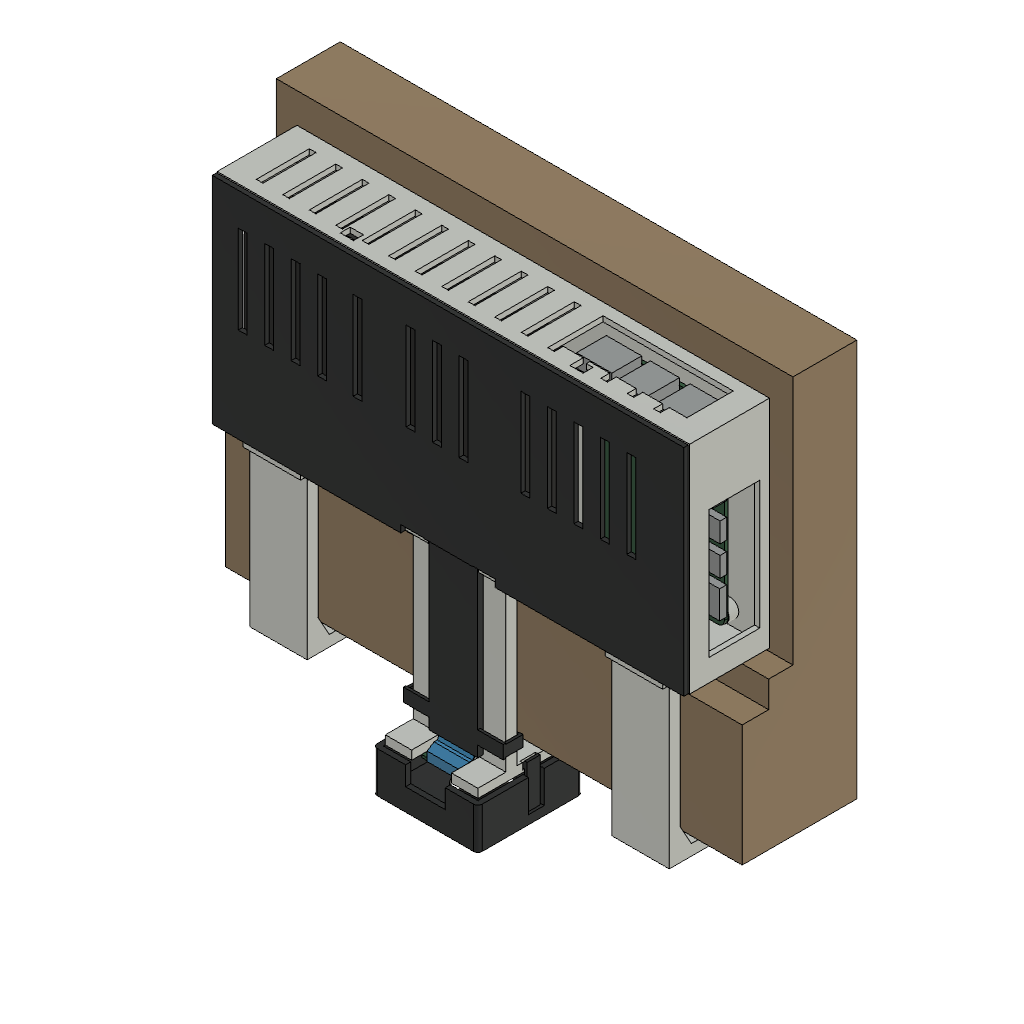
doorframe-camera-simple-v7 (Autodesk Fusion 360 design; units mm, degrees)
part number: 2026-11-08-18-06-19-159
part number: 2026-11-08-18-06-29-546
part number: 2026-11-08-18-06-30-123
part number: 2026-11-08-18-06-42-850
part number: 2026-11-08-20-43-14-141
part number: 2026-11-08-20-43-15-002
part number: 2026-11-08-20-43-15-243
part number: 2026-11-08-21-23-27-700
part number: 2026-11-08-21-23-30-854
part number: 2026-11-08-21-23-35-208
part number: 2026-11-08-21-23-36-761
part number: 2026-11-08-21-25-22-931
Autodesk Fusion 360 part; units mm, degrees
(part 1 of 2)
ref_plane "WorkPlane1" through (0, 0, 4.4) normal (0, 0, 1) x (1, 0, 0) in component "REFERENCE - INIU P51L-E2 115 x 73 x 29 mm"
sketch "INIU envelope - check supplied cable position outline" plane through (0, 0, 4.4) normal (0, 0, 1) x (1, 0, 0) in component "REFERENCE - INIU P51L-E2 115 x 73 x 29 mm"
  line L0 (11, 7.5) -> (116, 7.5)
  line L1 (121, 12.5) -> (121, 75.5)
  line L2 (116, 80.5) -> (11, 80.5)
  line L3 (6, 75.5) -> (6, 12.5)
  arc A0 (116, 7.5) -> (121, 12.5) centre (116, 12.5) ccw
  arc A1 (121, 75.5) -> (116, 80.5) centre (116, 75.5) ccw
  arc A2 (11, 80.5) -> (6, 75.5) centre (11, 75.5) ccw
  arc A3 (6, 12.5) -> (11, 7.5) centre (11, 12.5) ccw
extrude "INIU envelope - check supplied cable position" add sketch "INIU envelope - check supplied cable position outline" along normal blind 29 makes body 1 in component "REFERENCE - INIU P51L-E2 115 x 73 x 29 mm"
ref_plane "WorkPlane1" through (0, 0, 44.4) normal (0, 0, 1) x (1, 0, 0) in component "REFERENCE - Raspberry Pi4 rotated ports"
sketch "Pi PCB 85 x 56 x 1.6 outline" plane through (0, 0, 44.4) normal (0, 0, 1) x (1, 0, 0) in component "REFERENCE - Raspberry Pi4 rotated ports"
  line L0 (9, 15) -> (88, 15)
  line L1 (91, 18) -> (91, 68)
  line L2 (88, 71) -> (9, 71)
  line L3 (6, 68) -> (6, 18)
  arc A0 (88, 15) -> (91, 18) centre (88, 18) ccw
  arc A1 (91, 68) -> (88, 71) centre (88, 68) ccw
  arc A2 (9, 71) -> (6, 68) centre (9, 68) ccw
  arc A3 (6, 18) -> (9, 15) centre (9, 18) ccw
extrude "Pi PCB 85 x 56 x 1.6" add sketch "Pi PCB 85 x 56 x 1.6 outline" along normal blind 1.6 separate body makes body 2 in component "REFERENCE - Raspberry Pi4 rotated ports"
ref_plane "WorkPlane2" through (0, 0, 44.3) normal (0, 0, 1) x (1, 0, 0) in component "REFERENCE - Raspberry Pi4 rotated ports"
sketch "Pi mounting holes layout" plane through (0, 0, 44.3) normal (0, 0, 1) x (1, 0, 0) in component "REFERENCE - Raspberry Pi4 rotated ports"
  circle A0 centre (87.5, 67.5) radius 1.375
  circle A1 centre (29.5, 67.5) radius 1.375
  circle A2 centre (87.5, 18.5) radius 1.375
  circle A3 centre (29.5, 18.5) radius 1.375
extrude "Pi mounting holes" cut sketch "Pi mounting holes layout" along normal blind 2 bodies 2 in component "REFERENCE - Raspberry Pi4 rotated ports"
ref_plane "WorkPlane3" through (0, 0, 46) normal (0, 0, 1) x (1, 0, 0) in component "REFERENCE - Raspberry Pi4 rotated ports"
sketch "USB3 outline" plane through (0, 0, 46) normal (0, 0, 1) x (1, 0, 0) in component "REFERENCE - Raspberry Pi4 rotated ports"
  line L0 (3, 55.4) -> (20.5, 55.4)
  line L1 (20.5, 55.4) -> (20.5, 68.6)
  line L2 (20.5, 68.6) -> (3, 68.6)
  line L3 (3, 68.6) -> (3, 55.4)
extrude "USB3" add sketch "USB3 outline" along normal blind 16 separate body makes body 3 in component "REFERENCE - Raspberry Pi4 rotated ports"
ref_plane "WorkPlane4" through (0, 0, 46) normal (0, 0, 1) x (1, 0, 0) in component "REFERENCE - Raspberry Pi4 rotated ports"
sketch "USB2 outline" plane through (0, 0, 46) normal (0, 0, 1) x (1, 0, 0) in component "REFERENCE - Raspberry Pi4 rotated ports"
  line L0 (3, 37.4) -> (20.5, 37.4)
  line L1 (20.5, 37.4) -> (20.5, 50.6)
  line L2 (20.5, 50.6) -> (3, 50.6)
  line L3 (3, 50.6) -> (3, 37.4)
extrude "USB2" add sketch "USB2 outline" along normal blind 16 separate body makes body 4 in component "REFERENCE - Raspberry Pi4 rotated ports"
ref_plane "WorkPlane5" through (0, 0, 46) normal (0, 0, 1) x (1, 0, 0) in component "REFERENCE - Raspberry Pi4 rotated ports"
sketch "Ethernet outline" plane through (0, 0, 46) normal (0, 0, 1) x (1, 0, 0) in component "REFERENCE - Raspberry Pi4 rotated ports"
  line L0 (3, 17.5) -> (24.5, 17.5)
  line L1 (24.5, 17.5) -> (24.5, 33.5)
  line L2 (24.5, 33.5) -> (3, 33.5)
  line L3 (3, 33.5) -> (3, 17.5)
extrude "Ethernet" add sketch "Ethernet outline" along normal blind 13.5 separate body makes body 5 in component "REFERENCE - Raspberry Pi4 rotated ports"
ref_plane "WorkPlane6" through (0, 0, 46) normal (0, 0, 1) x (1, 0, 0) in component "REFERENCE - Raspberry Pi4 rotated ports"
sketch "USB-C outline" plane through (0, 0, 46) normal (0, 0, 1) x (1, 0, 0) in component "REFERENCE - Raspberry Pi4 rotated ports"
  line L0 (73.5, 64) -> (86.1, 64)
  line L1 (86.1, 64) -> (86.1, 72)
  line L2 (86.1, 72) -> (73.5, 72)
  line L3 (73.5, 72) -> (73.5, 64)
extrude "USB-C" add sketch "USB-C outline" along normal blind 3.2 separate body makes body 6 in component "REFERENCE - Raspberry Pi4 rotated ports"
ref_plane "WorkPlane7" through (0, 0, 46) normal (0, 0, 1) x (1, 0, 0) in component "REFERENCE - Raspberry Pi4 rotated ports"
sketch "HDMI0 outline" plane through (0, 0, 46) normal (0, 0, 1) x (1, 0, 0) in component "REFERENCE - Raspberry Pi4 rotated ports"
  line L0 (60.5, 64) -> (69.5, 64)
  line L1 (69.5, 64) -> (69.5, 72)
  line L2 (69.5, 72) -> (60.5, 72)
  line L3 (60.5, 72) -> (60.5, 64)
extrude "HDMI0" add sketch "HDMI0 outline" along normal blind 3 separate body makes body 7 in component "REFERENCE - Raspberry Pi4 rotated ports"
ref_plane "WorkPlane8" through (0, 0, 46) normal (0, 0, 1) x (1, 0, 0) in component "REFERENCE - Raspberry Pi4 rotated ports"
sketch "HDMI1 outline" plane through (0, 0, 46) normal (0, 0, 1) x (1, 0, 0) in component "REFERENCE - Raspberry Pi4 rotated ports"
  line L0 (47, 64) -> (56, 64)
  line L1 (56, 64) -> (56, 72)
  line L2 (56, 72) -> (47, 72)
  line L3 (47, 72) -> (47, 64)
extrude "HDMI1" add sketch "HDMI1 outline" along normal blind 3 separate body makes body 8 in component "REFERENCE - Raspberry Pi4 rotated ports"
ref_plane "WorkPlane9" through (0, 0, 46) normal (0, 0, 1) x (1, 0, 0) in component "REFERENCE - Raspberry Pi4 rotated ports"
sketch "Audio outline" plane through (0, 0, 46) normal (0, 0, 1) x (1, 0, 0) in component "REFERENCE - Raspberry Pi4 rotated ports"
  line L0 (33.5, 58) -> (40.5, 58)
  line L1 (40.5, 58) -> (40.5, 72)
  line L2 (40.5, 72) -> (33.5, 72)
  line L3 (33.5, 72) -> (33.5, 58)
extrude "Audio" add sketch "Audio outline" along normal blind 6 separate body makes body 9 in component "REFERENCE - Raspberry Pi4 rotated ports"
ref_plane "WorkPlane1" through (0, 0, 5.5) normal (0, 0, 1) x (1, 0, 0) in component "REFERENCE - Waveshare RPi Camera G PCB and lens"
sketch "Camera PCB 25 x 24 outline" plane through (0, 0, 5.5) normal (0, 0, 1) x (1, 0, 0) in component "REFERENCE - Waveshare RPi Camera G PCB and lens"
  line L0 (6.5, 6) -> (31.5, 6)
  line L1 (31.5, 6) -> (31.5, 30)
  line L2 (31.5, 30) -> (6.5, 30)
  line L3 (6.5, 30) -> (6.5, 6)
extrude "Camera PCB 25 x 24" add sketch "Camera PCB 25 x 24 outline" along normal blind 1.2 separate body makes body 10 in component "REFERENCE - Waveshare RPi Camera G PCB and lens"
ref_plane "WorkPlane2" through (0, 0, 5.4) normal (0, 0, 1) x (1, 0, 0) in component "REFERENCE - Waveshare RPi Camera G PCB and lens"
sketch "Camera mounting holes layout" plane through (0, 0, 5.4) normal (0, 0, 1) x (1, 0, 0) in component "REFERENCE - Waveshare RPi Camera G PCB and lens"
  circle A0 centre (8.5, 14.5) radius 1.1
  circle A1 centre (29.5, 14.5) radius 1.1
  circle A2 centre (8.5, 28) radius 1.1
  circle A3 centre (29.5, 28) radius 1.1
extrude "Camera mounting holes" cut sketch "Camera mounting holes layout" along normal blind 1.5 bodies 10 in component "REFERENCE - Waveshare RPi Camera G PCB and lens"
ref_plane "WorkPlane3" through (0, 0, 6.7) normal (0, 0, 1) x (1, 0, 0) in component "REFERENCE - Waveshare RPi Camera G PCB and lens"
sketch "Approximate fisheye barrel - verify height layout" plane through (0, 0, 6.7) normal (0, 0, 1) x (1, 0, 0) in component "REFERENCE - Waveshare RPi Camera G PCB and lens"
  circle A0 centre (19, 21.65) radius 8
extrude "Approximate fisheye barrel - verify height" add sketch "Approximate fisheye barrel - verify height layout" along normal blind 18 separate body makes body 11 in component "REFERENCE - Waveshare RPi Camera G PCB and lens"
ref_plane "WorkPlane1" through (0, 0, 55) normal (0, 0, 1) x (1, 0, 0) in component "REFERENCE - six mount pads - compressed"
sketch "left lower-ledge pad - 20 x 10 x 3 outline" plane through (0, 0, 55) normal (0, 0, 1) x (1, 0, 0) in component "REFERENCE - six mount pads - compressed"
  line L0 (15, 0.5) -> (35, 0.5)
  line L1 (35, 0.5) -> (35, 10.5)
  line L2 (35, 10.5) -> (15, 10.5)
  line L3 (15, 10.5) -> (15, 0.5)
extrude "left lower-ledge pad - 20 x 10 x 3" add sketch "left lower-ledge pad - 20 x 10 x 3 outline" along normal blind 2.5 separate body makes body 12 in component "REFERENCE - six mount pads - compressed"
ref_plane "WorkPlane2" through (0, 0, 67) normal (0, 0, 1) x (1, 0, 0) in component "REFERENCE - six mount pads - compressed"
sketch "left upper-ledge pad - 20 x 9 x 3 outline" plane through (0, 0, 67) normal (0, 0, 1) x (1, 0, 0) in component "REFERENCE - six mount pads - compressed"
  line L0 (15, 13) -> (35, 13)
  line L1 (35, 13) -> (35, 22)
  line L2 (35, 22) -> (15, 22)
  line L3 (15, 22) -> (15, 13)
extrude "left upper-ledge pad - 20 x 9 x 3" add sketch "left upper-ledge pad - 20 x 9 x 3 outline" along normal blind 2.5 separate body makes body 13 in component "REFERENCE - six mount pads - compressed"
ref_plane "WorkPlane3" through (0, 0, -2.5) normal (0, 0, 1) x (1, 0, 0) in component "REFERENCE - six mount pads - compressed"
sketch "left underside retaining pad - 16 x 14 x 3 outline" plane through (0, 0, -2.5) normal (0, 0, 1) x (1, 0, 0) in component "REFERENCE - six mount pads - compressed"
  line L0 (17, 30) -> (33, 30)
  line L1 (33, 30) -> (33, 44)
  line L2 (33, 44) -> (17, 44)
  line L3 (17, 44) -> (17, 30)
extrude "left underside retaining pad - 16 x 14 x 3" add sketch "left underside retaining pad - 16 x 14 x 3 outline" along normal blind 2.5 separate body makes body 14 in component "REFERENCE - six mount pads - compressed"
ref_plane "WorkPlane4" through (0, 0, 55) normal (0, 0, 1) x (1, 0, 0) in component "REFERENCE - six mount pads - compressed"
sketch "right lower-ledge pad - 20 x 10 x 3 outline" plane through (0, 0, 55) normal (0, 0, 1) x (1, 0, 0) in component "REFERENCE - six mount pads - compressed"
  line L0 (179, 0.5) -> (199, 0.5)
  line L1 (199, 0.5) -> (199, 10.5)
  line L2 (199, 10.5) -> (179, 10.5)
  line L3 (179, 10.5) -> (179, 0.5)
extrude "right lower-ledge pad - 20 x 10 x 3" add sketch "right lower-ledge pad - 20 x 10 x 3 outline" along normal blind 2.5 separate body makes body 15 in component "REFERENCE - six mount pads - compressed"
ref_plane "WorkPlane5" through (0, 0, 67) normal (0, 0, 1) x (1, 0, 0) in component "REFERENCE - six mount pads - compressed"
sketch "right upper-ledge pad - 20 x 9 x 3 outline" plane through (0, 0, 67) normal (0, 0, 1) x (1, 0, 0) in component "REFERENCE - six mount pads - compressed"
  line L0 (179, 13) -> (199, 13)
  line L1 (199, 13) -> (199, 22)
  line L2 (199, 22) -> (179, 22)
  line L3 (179, 22) -> (179, 13)
extrude "right upper-ledge pad - 20 x 9 x 3" add sketch "right upper-ledge pad - 20 x 9 x 3 outline" along normal blind 2.5 separate body makes body 16 in component "REFERENCE - six mount pads - compressed"
ref_plane "WorkPlane6" through (0, 0, -2.5) normal (0, 0, 1) x (1, 0, 0) in component "REFERENCE - six mount pads - compressed"
sketch "right underside retaining pad - 16 x 14 x 3 outline" plane through (0, 0, -2.5) normal (0, 0, 1) x (1, 0, 0) in component "REFERENCE - six mount pads - compressed"
  line L0 (181, 30) -> (197, 30)
  line L1 (197, 30) -> (197, 44)
  line L2 (197, 44) -> (181, 44)
  line L3 (181, 44) -> (181, 30)
extrude "right underside retaining pad - 16 x 14 x 3" add sketch "right underside retaining pad - 16 x 14 x 3 outline" along normal blind 2.5 separate body makes body 17 in component "REFERENCE - six mount pads - compressed"
ref_plane "WorkPlane1" through (-10, 0, 0) normal (1, 0, 0) x (0, 1, 0) in component "REFERENCE - upward-stepped frame - back wall assumed"
sketch "Corrected upward frame outline" plane through (-10, 0, 0) normal (1, 0, 0) x (0, 0, -1) in component "REFERENCE - upward-stepped frame - back wall assumed"
  line L0 (0, 0) -> (0, 52)
  line L1 (0, 52) -> (-180, 52)
  line L2 (-180, 52) -> (-180, 23)
  line L3 (-180, 23) -> (-67, 23)
  line L4 (-67, 23) -> (-67, 12)
  line L5 (-67, 12) -> (-55, 12)
  line L6 (-55, 12) -> (-55, 0)
  line L7 (-55, 0) -> (0, 0)
extrude "Corrected upward frame" add sketch "Corrected upward frame outline" along normal blind 234 separate body makes body 18 in component "REFERENCE - upward-stepped frame - back wall assumed"
ref_plane "WorkPlane1" through (245, 0, 0) normal (1, 0, 0) x (0, 1, 0) in component "07 Upward-step fit gauge PRINT FIRST - PRINT"
sketch "Profile fit gauge outline" plane through (245, 0, 0) normal (1, 0, 0) x (0, 0, -1) in component "07 Upward-step fit gauge PRINT FIRST - PRINT"
  line L0 (0, -0.6) -> (-55.6, -0.6)
  line L1 (-55.6, -0.6) -> (-55.6, 11.4)
  line L2 (-55.6, 11.4) -> (-67.6, 11.4)
  line L3 (-67.6, 11.4) -> (-67.6, 23)
  line L4 (-67.6, 23) -> (-70, 23)
  line L5 (-70, 23) -> (-70, 9)
  line L6 (-70, 9) -> (-58, 9)
  line L7 (-58, 9) -> (-58, -3)
  line L8 (-58, -3) -> (0, -3)
  line L9 (0, -3) -> (0, -0.6)
extrude "Profile fit gauge" add sketch "Profile fit gauge outline" along normal blind 8 separate body makes body 19 in component "07 Upward-step fit gauge PRINT FIRST - PRINT"
ref_plane "WorkPlane1" through (0, 0, 69) normal (0, 0, 1) x (1, 0, 0) in component "01 Integral case mount and camera holder - PRINT"
sketch "Open-front case outline" plane through (0, 0, 69) normal (0, 0, 1) x (1, 0, 0) in component "01 Integral case mount and camera holder - PRINT"
  line L0 (0, -13.8) -> (214, -13.8)
  line L1 (214, -13.8) -> (214, 22.4)
  line L2 (214, 22.4) -> (0, 22.4)
  line L3 (0, 22.4) -> (0, -13.8)
extrude "Open-front case" add sketch "Open-front case outline" along normal blind 98 separate body makes body 20 in component "01 Integral case mount and camera holder - PRINT"
ref_plane "WorkPlane2" through (0, 0, 71.4) normal (0, 0, 1) x (1, 0, 0) in component "01 Integral case mount and camera holder - PRINT"
sketch "Electronics cavity outline" plane through (0, 0, 71.4) normal (0, 0, 1) x (1, 0, 0) in component "01 Integral case mount and camera holder - PRINT"
  line L0 (2.4, -14) -> (211.6, -14)
  line L1 (211.6, -14) -> (211.6, 20)
  line L2 (211.6, 20) -> (2.4, 20)
  line L3 (2.4, 20) -> (2.4, -14)
extrude "Electronics cavity" cut sketch "Electronics cavity outline" along normal blind 93.2 bodies 20 in component "01 Integral case mount and camera holder - PRINT"
ref_plane "WorkPlane3" through (0, 20, 0) normal (0, 1, 0) x (0, 0, 1) in component "01 Integral case mount and camera holder - PRINT"
sketch "Pi heat-set bosses - 8 mm OD layout" plane through (0, 20, 0) normal (0, 1, 0) x (1, 0, 0) in component "01 Integral case mount and camera holder - PRINT"
  circle A0 centre (149.5, -78.5) radius 4
  circle A1 centre (198.5, -78.5) radius 4
  circle A2 centre (149.5, -136.5) radius 4
  circle A3 centre (198.5, -136.5) radius 4
extrude "Pi heat-set bosses - 8 mm OD" add sketch "Pi heat-set bosses - 8 mm OD layout" against normal blind 4.4 bodies 20 in component "01 Integral case mount and camera holder - PRINT"
ref_plane "WorkPlane4" through (0, 15.6, 0) normal (0, 1, 0) x (0, 0, 1) in component "01 Integral case mount and camera holder - PRINT"
sketch "Pi M2.5 insert pockets - 4 mm x 5 mm layout" plane through (0, 15.6, 0) normal (0, 1, 0) x (1, 0, 0) in component "01 Integral case mount and camera holder - PRINT"
  circle A0 centre (149.5, -78.5) radius 2
  circle A1 centre (198.5, -78.5) radius 2
  circle A2 centre (149.5, -136.5) radius 2
  circle A3 centre (198.5, -136.5) radius 2
extrude "Pi M2.5 insert pockets - 4 mm x 5 mm" cut sketch "Pi M2.5 insert pockets - 4 mm x 5 mm layout" along normal blind 5 bodies 20 in component "01 Integral case mount and camera holder - PRINT"
ref_plane "WorkPlane5" through (0, 0, 79) normal (0, 0, 1) x (1, 0, 0) in component "01 Integral case mount and camera holder - PRINT"
sketch "Pi power HDMI and audio side access outline" plane through (0, 0, 79) normal (0, 0, 1) x (1, 0, 0) in component "01 Integral case mount and camera holder - PRINT"
  line L0 (210.8, -5) -> (215, -5)
  line L1 (215, -5) -> (215, 18)
  line L2 (215, 18) -> (210.8, 18)
  line L3 (210.8, 18) -> (210.8, -5)
extrude "Pi power HDMI and audio side access" cut sketch "Pi power HDMI and audio side access outline" along normal blind 58 bodies 20 in component "01 Integral case mount and camera holder - PRINT"
ref_plane "WorkPlane6" through (0, 0, 75) normal (0, 0, 1) x (1, 0, 0) in component "01 Integral case mount and camera holder - PRINT"
sketch "Battery charging-end access outline" plane through (0, 0, 75) normal (0, 0, 1) x (1, 0, 0) in component "01 Integral case mount and camera holder - PRINT"
  line L0 (-1, -11.5) -> (3.2, -11.5)
  line L1 (3.2, -11.5) -> (3.2, 20.5)
  line L2 (3.2, 20.5) -> (-1, 20.5)
  line L3 (-1, 20.5) -> (-1, -11.5)
extrude "Battery charging-end access" cut sketch "Battery charging-end access outline" along normal blind 77 bodies 20 in component "01 Integral case mount and camera holder - PRINT"
ref_plane "WorkPlane7" through (0, 0, 164.5) normal (0, 0, 1) x (1, 0, 0) in component "01 Integral case mount and camera holder - PRINT"
sketch "Roof vents layout" plane through (0, 0, 164.5) normal (0, 0, 1) x (1, 0, 0) in component "01 Integral case mount and camera holder - PRINT"
  line L0 (12, -8) -> (15, -8)
  line L1 (15, -8) -> (15, 16)
  line L2 (15, 16) -> (12, 16)
  line L3 (12, 16) -> (12, -8)
  line L4 (24, -8) -> (27, -8)
  line L5 (27, -8) -> (27, 16)
  line L6 (27, 16) -> (24, 16)
  line L7 (24, 16) -> (24, -8)
  line L8 (36, -8) -> (39, -8)
  line L9 (39, -8) -> (39, 16)
  line L10 (39, 16) -> (36, 16)
  line L11 (36, 16) -> (36, -8)
  line L12 (48, -8) -> (51, -8)
  line L13 (51, -8) -> (51, 16)
  line L14 (51, 16) -> (48, 16)
  line L15 (48, 16) -> (48, -8)
  line L16 (60, -8) -> (63, -8)
  line L17 (63, -8) -> (63, 16)
  line L18 (63, 16) -> (60, 16)
  line L19 (60, 16) -> (60, -8)
  line L20 (72, -8) -> (75, -8)
  line L21 (75, -8) -> (75, 16)
  line L22 (75, 16) -> (72, 16)
  line L23 (72, 16) -> (72, -8)
  line L24 (84, -8) -> (87, -8)
  line L25 (87, -8) -> (87, 16)
  line L26 (87, 16) -> (84, 16)
  line L27 (84, 16) -> (84, -8)
  line L28 (96, -8) -> (99, -8)
  line L29 (99, -8) -> (99, 16)
  line L30 (99, 16) -> (96, 16)
  line L31 (96, 16) -> (96, -8)
  line L32 (108, -8) -> (111, -8)
  line L33 (111, -8) -> (111, 16)
  line L34 (111, 16) -> (108, 16)
  line L35 (108, 16) -> (108, -8)
  line L36 (120, -8) -> (123, -8)
  line L37 (123, -8) -> (123, 16)
  line L38 (123, 16) -> (120, 16)
  line L39 (120, 16) -> (120, -8)
  line L40 (132, -8) -> (135, -8)
  line L41 (135, -8) -> (135, 16)
  line L42 (135, 16) -> (132, 16)
  line L43 (132, 16) -> (132, -8)
  line L44 (144, -8) -> (147, -8)
  line L45 (147, -8) -> (147, 16)
  line L46 (147, 16) -> (144, 16)
  line L47 (144, 16) -> (144, -8)
  line L48 (156, -8) -> (159, -8)
  line L49 (159, -8) -> (159, 16)
  line L50 (159, 16) -> (156, 16)
  line L51 (156, 16) -> (156, -8)
  line L52 (168, -8) -> (171, -8)
  line L53 (171, -8) -> (171, 16)
  line L54 (171, 16) -> (168, 16)
  line L55 (168, 16) -> (168, -8)
  line L56 (180, -8) -> (183, -8)
  line L57 (183, -8) -> (183, 16)
  line L58 (183, 16) -> (180, 16)
  line L59 (180, 16) -> (180, -8)
  line L60 (192, -8) -> (195, -8)
  line L61 (195, -8) -> (195, 16)
  line L62 (195, 16) -> (192, 16)
  line L63 (192, 16) -> (192, -8)
extrude "Roof vents" cut sketch "Roof vents layout" along normal blind 2.6 bodies 20 in component "01 Integral case mount and camera holder - PRINT"
ref_plane "WorkPlane8" through (0, 0, 164.5) normal (0, 0, 1) x (1, 0, 0) in component "01 Integral case mount and camera holder - PRINT"
sketch "Pi USB and Ethernet top access outline" plane through (0, 0, 164.5) normal (0, 0, 1) x (1, 0, 0) in component "01 Integral case mount and camera holder - PRINT"
  line L0 (144, -4) -> (203, -4)
  line L1 (203, -4) -> (203, 17)
  line L2 (203, 17) -> (144, 17)
  line L3 (144, 17) -> (144, -4)
extrude "Pi USB and Ethernet top access" cut sketch "Pi USB and Ethernet top access outline" along normal blind 2.6 bodies 20 in component "01 Integral case mount and camera holder - PRINT"
ref_plane "WorkPlane9" through (0, 0, 68.9) normal (0, 0, 1) x (1, 0, 0) in component "01 Integral case mount and camera holder - PRINT"
sketch "Battery strap slots layout" plane through (0, 0, 68.9) normal (0, 0, 1) x (1, 0, 0) in component "01 Integral case mount and camera holder - PRINT"
  line L0 (38, -10.8) -> (50, -10.8)
  line L1 (50, -10.8) -> (50, -8.6)
  line L2 (50, -8.6) -> (38, -8.6)
  line L3 (38, -8.6) -> (38, -10.8)
  line L4 (38, 18.6) -> (50, 18.6)
  line L5 (50, 18.6) -> (50, 20.8)
  line L6 (50, 20.8) -> (38, 20.8)
  line L7 (38, 20.8) -> (38, 18.6)
  line L8 (80, -10.8) -> (92, -10.8)
  line L9 (92, -10.8) -> (92, -8.6)
  line L10 (92, -8.6) -> (80, -8.6)
  line L11 (80, -8.6) -> (80, -10.8)
  line L12 (80, 18.6) -> (92, 18.6)
  line L13 (92, 18.6) -> (92, 20.8)
  line L14 (92, 20.8) -> (80, 20.8)
  line L15 (80, 20.8) -> (80, 18.6)
extrude "Battery strap slots" cut sketch "Battery strap slots layout" along normal blind 2.6 bodies 20 in component "01 Integral case mount and camera holder - PRINT"
ref_plane "WorkPlane10" through (0, 0, 57.5) normal (0, 0, 1) x (1, 0, 0) in component "01 Integral case mount and camera holder - PRINT"
sketch "First-ledge foot 1 outline" plane through (0, 0, 57.5) normal (0, 0, 1) x (1, 0, 0) in component "01 Integral case mount and camera holder - PRINT"
  line L0 (15, 0.5) -> (35, 0.5)
  line L1 (35, 0.5) -> (35, 10.5)
  line L2 (35, 10.5) -> (15, 10.5)
  line L3 (15, 10.5) -> (15, 0.5)
extrude "First-ledge foot 1" add sketch "First-ledge foot 1 outline" along normal blind 11.5 bodies 20 in component "01 Integral case mount and camera holder - PRINT"
ref_plane "WorkPlane11" through (0, 0, 65) normal (0, 0, 1) x (1, 0, 0) in component "01 Integral case mount and camera holder - PRINT"
sketch "Integral arm root 1 outline" plane through (0, 0, 65) normal (0, 0, 1) x (1, 0, 0) in component "01 Integral case mount and camera holder - PRINT"
  line L0 (12, -14) -> (38, -14)
  line L1 (38, -14) -> (38, -3)
  line L2 (38, -3) -> (12, -3)
  line L3 (12, -3) -> (12, -14)
extrude "Integral arm root 1" add sketch "Integral arm root 1 outline" along normal blind 4.2 bodies 20 in component "01 Integral case mount and camera holder - PRINT"
ref_plane "WorkPlane12" through (12, 0, 0) normal (1, 0, 0) x (0, 1, 0) in component "01 Integral case mount and camera holder - PRINT"
sketch "Integral retaining arm 1 outline" plane through (12, 0, 0) normal (1, 0, 0) x (0, 0, -1) in component "01 Integral case mount and camera holder - PRINT"
  line L0 (7, -11) -> (7, 45)
  line L1 (7, 45) -> (2, 45)
  line L2 (2, 45) -> (2, -1)
  line L3 (2, -1) -> (-7, -6)
  line L4 (-7, -6) -> (-66, -6)
  line L5 (-66, -6) -> (-66, -11)
  line L6 (-66, -11) -> (7, -11)
extrude "Integral retaining arm 1" add sketch "Integral retaining arm 1 outline" along normal blind 26 bodies 20 in component "01 Integral case mount and camera holder - PRINT"
ref_plane "WorkPlane13" through (0, 0, -2.5) normal (0, 0, 1) x (1, 0, 0) in component "01 Integral case mount and camera holder - PRINT"
sketch "Underside pad pocket 1 layout" plane through (0, 0, -2.5) normal (0, 0, 1) x (1, 0, 0) in component "01 Integral case mount and camera holder - PRINT"
  line L0 (17, 30) -> (33, 30)
  line L1 (33, 30) -> (33, 44)
  line L2 (33, 44) -> (17, 44)
  line L3 (17, 44) -> (17, 30)
extrude "Underside pad pocket 1" cut sketch "Underside pad pocket 1 layout" along normal blind 0.6 bodies 20 in component "01 Integral case mount and camera holder - PRINT"
ref_plane "WorkPlane14" through (11.9, 0, 0) normal (1, 0, 0) x (0, 1, 0) in component "01 Integral case mount and camera holder - PRINT"
sketch "Arm lead-in 1 outline" plane through (11.9, 0, 0) normal (1, 0, 0) x (0, 0, -1) in component "01 Integral case mount and camera holder - PRINT"
  line L0 (2, 44.5) -> (2, 45)
  line L1 (2, 45) -> (2.5, 45)
  line L2 (2.5, 45) -> (2, 44.5)
extrude "Arm lead-in 1" cut sketch "Arm lead-in 1 outline" along normal blind 26.2 bodies 20 in component "01 Integral case mount and camera holder - PRINT"
ref_plane "WorkPlane15" through (0, 0, 57.5) normal (0, 0, 1) x (1, 0, 0) in component "01 Integral case mount and camera holder - PRINT"
sketch "First-ledge foot 2 outline" plane through (0, 0, 57.5) normal (0, 0, 1) x (1, 0, 0) in component "01 Integral case mount and camera holder - PRINT"
  line L0 (179, 0.5) -> (199, 0.5)
  line L1 (199, 0.5) -> (199, 10.5)
  line L2 (199, 10.5) -> (179, 10.5)
  line L3 (179, 10.5) -> (179, 0.5)
extrude "First-ledge foot 2" add sketch "First-ledge foot 2 outline" along normal blind 11.5 bodies 20 in component "01 Integral case mount and camera holder - PRINT"
ref_plane "WorkPlane16" through (0, 0, 65) normal (0, 0, 1) x (1, 0, 0) in component "01 Integral case mount and camera holder - PRINT"
sketch "Integral arm root 2 outline" plane through (0, 0, 65) normal (0, 0, 1) x (1, 0, 0) in component "01 Integral case mount and camera holder - PRINT"
  line L0 (176, -14) -> (202, -14)
  line L1 (202, -14) -> (202, -3)
  line L2 (202, -3) -> (176, -3)
  line L3 (176, -3) -> (176, -14)
extrude "Integral arm root 2" add sketch "Integral arm root 2 outline" along normal blind 4.2 bodies 20 in component "01 Integral case mount and camera holder - PRINT"
ref_plane "WorkPlane17" through (176, 0, 0) normal (1, 0, 0) x (0, 1, 0) in component "01 Integral case mount and camera holder - PRINT"
sketch "Integral retaining arm 2 outline" plane through (176, 0, 0) normal (1, 0, 0) x (0, 0, -1) in component "01 Integral case mount and camera holder - PRINT"
  line L0 (7, -11) -> (7, 45)
  line L1 (7, 45) -> (2, 45)
  line L2 (2, 45) -> (2, -1)
  line L3 (2, -1) -> (-7, -6)
  line L4 (-7, -6) -> (-66, -6)
  line L5 (-66, -6) -> (-66, -11)
  line L6 (-66, -11) -> (7, -11)
extrude "Integral retaining arm 2" add sketch "Integral retaining arm 2 outline" along normal blind 26 bodies 20 in component "01 Integral case mount and camera holder - PRINT"
ref_plane "WorkPlane18" through (0, 0, -2.5) normal (0, 0, 1) x (1, 0, 0) in component "01 Integral case mount and camera holder - PRINT"
sketch "Underside pad pocket 2 layout" plane through (0, 0, -2.5) normal (0, 0, 1) x (1, 0, 0) in component "01 Integral case mount and camera holder - PRINT"
  line L0 (181, 30) -> (197, 30)
  line L1 (197, 30) -> (197, 44)
  line L2 (197, 44) -> (181, 44)
  line L3 (181, 44) -> (181, 30)
extrude "Underside pad pocket 2" cut sketch "Underside pad pocket 2 layout" along normal blind 0.6 bodies 20 in component "01 Integral case mount and camera holder - PRINT"
ref_plane "WorkPlane19" through (175.9, 0, 0) normal (1, 0, 0) x (0, 1, 0) in component "01 Integral case mount and camera holder - PRINT"
sketch "Arm lead-in 2 outline" plane through (175.9, 0, 0) normal (1, 0, 0) x (0, 0, -1) in component "01 Integral case mount and camera holder - PRINT"
  line L0 (2, 44.5) -> (2, 45)
  line L1 (2, 45) -> (2.5, 45)
  line L2 (2.5, 45) -> (2, 44.5)
extrude "Arm lead-in 2" cut sketch "Arm lead-in 2 outline" along normal blind 26.2 bodies 20 in component "01 Integral case mount and camera holder - PRINT"
ref_plane "WorkPlane20" through (0, 0, 68.9) normal (0, 0, 1) x (1, 0, 0) in component "01 Integral case mount and camera holder - PRINT"
sketch "Upper-ledge pad recesses layout" plane through (0, 0, 68.9) normal (0, 0, 1) x (1, 0, 0) in component "01 Integral case mount and camera holder - PRINT"
  line L0 (15, 13) -> (35, 13)
  line L1 (35, 13) -> (35, 22)
  line L2 (35, 22) -> (15, 22)
  line L3 (15, 22) -> (15, 13)
  line L4 (179, 13) -> (199, 13)
  line L5 (199, 13) -> (199, 22)
  line L6 (199, 22) -> (179, 22)
  line L7 (179, 22) -> (179, 13)
extrude "Upper-ledge pad recesses" cut sketch "Upper-ledge pad recesses layout" along normal blind 0.6 bodies 20 in component "01 Integral case mount and camera holder - PRINT"
ref_plane "WorkPlane21" through (0, 0, 68.9) normal (0, 0, 1) x (1, 0, 0) in component "01 Integral case mount and camera holder - PRINT"
sketch "Bottom cover latch window 55 outline" plane through (0, 0, 68.9) normal (0, 0, 1) x (1, 0, 0) in component "01 Integral case mount and camera holder - PRINT"
  line L0 (52, -5) -> (58, -5)
  line L1 (58, -5) -> (58, -0.5)
  line L2 (58, -0.5) -> (52, -0.5)
  line L3 (52, -0.5) -> (52, -5)
extrude "Bottom cover latch window 55" cut sketch "Bottom cover latch window 55 outline" along normal blind 2.6 bodies 20 in component "01 Integral case mount and camera holder - PRINT"
ref_plane "WorkPlane22" through (0, 0, 164.5) normal (0, 0, 1) x (1, 0, 0) in component "01 Integral case mount and camera holder - PRINT"
sketch "Top cover latch window 55 outline" plane through (0, 0, 164.5) normal (0, 0, 1) x (1, 0, 0) in component "01 Integral case mount and camera holder - PRINT"
  line L0 (52, -10) -> (58, -10)
  line L1 (58, -10) -> (58, -5.5)
  line L2 (58, -5.5) -> (52, -5.5)
  line L3 (52, -5.5) -> (52, -10)
extrude "Top cover latch window 55" cut sketch "Top cover latch window 55 outline" along normal blind 2.6 bodies 20 in component "01 Integral case mount and camera holder - PRINT"
ref_plane "WorkPlane23" through (0, 0, 68.9) normal (0, 0, 1) x (1, 0, 0) in component "01 Integral case mount and camera holder - PRINT"
sketch "Bottom cover latch window 159 outline" plane through (0, 0, 68.9) normal (0, 0, 1) x (1, 0, 0) in component "01 Integral case mount and camera holder - PRINT"
  line L0 (156, -5) -> (162, -5)
  line L1 (162, -5) -> (162, -0.5)
  line L2 (162, -0.5) -> (156, -0.5)
  line L3 (156, -0.5) -> (156, -5)
extrude "Bottom cover latch window 159" cut sketch "Bottom cover latch window 159 outline" along normal blind 2.6 bodies 20 in component "01 Integral case mount and camera holder - PRINT"
ref_plane "WorkPlane24" through (0, 0, 164.5) normal (0, 0, 1) x (1, 0, 0) in component "01 Integral case mount and camera holder - PRINT"
sketch "Top cover latch window 159 outline" plane through (0, 0, 164.5) normal (0, 0, 1) x (1, 0, 0) in component "01 Integral case mount and camera holder - PRINT"
  line L0 (156, -10) -> (162, -10)
  line L1 (162, -10) -> (162, -5.5)
  line L2 (162, -5.5) -> (156, -5.5)
  line L3 (156, -5.5) -> (156, -10)
extrude "Top cover latch window 159" cut sketch "Top cover latch window 159 outline" along normal blind 2.6 bodies 20 in component "01 Integral case mount and camera holder - PRINT"
ref_plane "WorkPlane25" through (0, 0, 69) normal (0, 0, 1) x (1, 0, 0) in component "01 Integral case mount and camera holder - PRINT"
sketch "Camera stem floor connection outline" plane through (0, 0, 69) normal (0, 0, 1) x (1, 0, 0) in component "01 Integral case mount and camera holder - PRINT"
  line L0 (86, -11) -> (128, -11)
  line L1 (128, -11) -> (128, -5)
  line L2 (128, -5) -> (86, -5)
  line L3 (86, -5) -> (86, -11)
extrude "Camera stem floor connection" add sketch "Camera stem floor connection outline" along normal blind 3 bodies 20 in component "01 Integral case mount and camera holder - PRINT"
ref_plane "WorkPlane26" through (0, 0, -6) normal (0, 0, 1) x (1, 0, 0) in component "01 Integral case mount and camera holder - PRINT"
sketch "Flush camera stem outline" plane through (0, 0, -6) normal (0, 0, 1) x (1, 0, 0) in component "01 Integral case mount and camera holder - PRINT"
  line L0 (86, -11) -> (128, -11)
  line L1 (128, -11) -> (128, -6)
  line L2 (128, -6) -> (86, -6)
  line L3 (86, -6) -> (86, -11)
extrude "Flush camera stem" add sketch "Flush camera stem outline" along normal blind 75.2 bodies 20 in component "01 Integral case mount and camera holder - PRINT"
ref_plane "WorkPlane27" through (0, 0, -10) normal (0, 0, 1) x (1, 0, 0) in component "01 Integral case mount and camera holder - PRINT"
sketch "Integral camera backplate outline" plane through (0, 0, -10) normal (0, 0, 1) x (1, 0, 0) in component "01 Integral case mount and camera holder - PRINT"
  line L0 (86, -23.65) -> (128, -23.65)
  line L1 (128, -23.65) -> (128, 18.35)
  line L2 (128, 18.35) -> (86, 18.35)
  line L3 (86, 18.35) -> (86, -23.65)
extrude "Integral camera backplate" add sketch "Integral camera backplate outline" along normal blind 4 bodies 20 in component "01 Integral case mount and camera holder - PRINT"
ref_plane "WorkPlane28" through (0, 0, -13.5) normal (0, 0, 1) x (1, 0, 0) in component "01 Integral case mount and camera holder - PRINT"
sketch "Camera M2 insert bosses - 6.4 mm OD layout" plane through (0, 0, -13.5) normal (0, 0, 1) x (1, 0, 0) in component "01 Integral case mount and camera holder - PRINT"
  circle A0 centre (117.5, -7.15) radius 3.2
  circle A1 centre (117.5, 6.35) radius 3.2
  circle A2 centre (96.5, -7.15) radius 3.2
  circle A3 centre (96.5, 6.35) radius 3.2
extrude "Camera M2 insert bosses - 6.4 mm OD" add sketch "Camera M2 insert bosses - 6.4 mm OD layout" along normal blind 3.5 bodies 20 in component "01 Integral case mount and camera holder - PRINT"
ref_plane "WorkPlane29" through (0, 0, -13.5) normal (0, 0, 1) x (1, 0, 0) in component "01 Integral case mount and camera holder - PRINT"
sketch "Camera M2 insert pockets - 3.2 mm x 4 mm layout" plane through (0, 0, -13.5) normal (0, 0, 1) x (1, 0, 0) in component "01 Integral case mount and camera holder - PRINT"
  circle A0 centre (117.5, -7.15) radius 1.6
  circle A1 centre (117.5, 6.35) radius 1.6
  circle A2 centre (96.5, -7.15) radius 1.6
  circle A3 centre (96.5, 6.35) radius 1.6
extrude "Camera M2 insert pockets - 3.2 mm x 4 mm" cut sketch "Camera M2 insert pockets - 3.2 mm x 4 mm layout" along normal blind 4 bodies 20 in component "01 Integral case mount and camera holder - PRINT"
ref_plane "WorkPlane30" through (0, 0, -10.1) normal (0, 0, 1) x (1, 0, 0) in component "01 Integral case mount and camera holder - PRINT"
sketch "Ribbon lower turn opening outline" plane through (0, 0, -10.1) normal (0, 0, 1) x (1, 0, 0) in component "01 Integral case mount and camera holder - PRINT"
  line L0 (98, -24) -> (116, -24)
  line L1 (116, -24) -> (116, -11.5)
  line L2 (116, -11.5) -> (98, -11.5)
  line L3 (98, -11.5) -> (98, -24)
extrude "Ribbon lower turn opening" cut sketch "Ribbon lower turn opening outline" along normal blind 4.2 bodies 20 in component "01 Integral case mount and camera holder - PRINT"
ref_plane "WorkPlane31" through (0, 0, -6) normal (0, 0, 1) x (1, 0, 0) in component "01 Integral case mount and camera holder - PRINT"
sketch "Recessed ribbon channel outline" plane through (0, 0, -6) normal (0, 0, 1) x (1, 0, 0) in component "01 Integral case mount and camera holder - PRINT"
  line L0 (98, -11.1) -> (116, -11.1)
  line L1 (116, -11.1) -> (116, -9.4)
  line L2 (116, -9.4) -> (98, -9.4)
  line L3 (98, -9.4) -> (98, -11.1)
extrude "Recessed ribbon channel" cut sketch "Recessed ribbon channel outline" along normal blind 75 bodies 20 in component "01 Integral case mount and camera holder - PRINT"
ref_plane "WorkPlane32" through (98, 0, 0) normal (1, 0, 0) x (0, 1, 0) in component "01 Integral case mount and camera holder - PRINT"
sketch "Ribbon entry guide ramp outline" plane through (98, 0, 0) normal (1, 0, 0) x (0, 0, -1) in component "01 Integral case mount and camera holder - PRINT"
  line L0 (-63, -9.4) -> (-69, -9.4)
  line L1 (-69, -9.4) -> (-69, -10)
  line L2 (-69, -10) -> (-63, -9.4)
extrude "Ribbon entry guide ramp" add sketch "Ribbon entry guide ramp outline" along normal blind 18 bodies 20 in component "01 Integral case mount and camera holder - PRINT"
ref_plane "WorkPlane33" through (0, 0, 68.9) normal (0, 0, 1) x (1, 0, 0) in component "01 Integral case mount and camera holder - PRINT"
sketch "Covered ribbon entry through floor outline" plane through (0, 0, 68.9) normal (0, 0, 1) x (1, 0, 0) in component "01 Integral case mount and camera holder - PRINT"
  line L0 (95.6, -14) -> (118.4, -14)
  line L1 (118.4, -14) -> (118.4, -9.8)
  line L2 (118.4, -9.8) -> (95.6, -9.8)
  line L3 (95.6, -9.8) -> (95.6, -14)
extrude "Covered ribbon entry through floor" cut sketch "Covered ribbon entry through floor outline" along normal blind 3.2 bodies 20 in component "01 Integral case mount and camera holder - PRINT"
ref_plane "WorkPlane34" through (0, 0, -9) normal (0, 0, 1) x (1, 0, 0) in component "01 Integral case mount and camera holder - PRINT"
sketch "L camera guard latch pocket outline" plane through (0, 0, -9) normal (0, 0, 1) x (1, 0, 0) in component "01 Integral case mount and camera holder - PRINT"
  line L0 (85.9, -3.4) -> (87.1, -3.4)
  line L1 (87.1, -3.4) -> (87.1, 3.4)
  line L2 (87.1, 3.4) -> (85.9, 3.4)
  line L3 (85.9, 3.4) -> (85.9, -3.4)
extrude "L camera guard latch pocket" cut sketch "L camera guard latch pocket outline" along normal blind 3.1 bodies 20 in component "01 Integral case mount and camera holder - PRINT"
ref_plane "WorkPlane35" through (0, 0, -9) normal (0, 0, 1) x (1, 0, 0) in component "01 Integral case mount and camera holder - PRINT"
sketch "R camera guard latch pocket outline" plane through (0, 0, -9) normal (0, 0, 1) x (1, 0, 0) in component "01 Integral case mount and camera holder - PRINT"
  line L0 (126.9, -3.4) -> (128.1, -3.4)
  line L1 (128.1, -3.4) -> (128.1, 3.4)
  line L2 (128.1, 3.4) -> (126.9, 3.4)
  line L3 (126.9, 3.4) -> (126.9, -3.4)
extrude "R camera guard latch pocket" cut sketch "R camera guard latch pocket outline" along normal blind 3.1 bodies 20 in component "01 Integral case mount and camera holder - PRINT"
ref_plane "WorkPlane1" through (0, 0, 69.2) normal (0, 0, 1) x (1, 0, 0) in component "02 Snap-on front cover - PRINT"
sketch "Front cover outline" plane through (0, 0, 69.2) normal (0, 0, 1) x (1, 0, 0) in component "02 Snap-on front cover - PRINT"
  line L0 (0.2, -16.2) -> (213.8, -16.2)
  line L1 (213.8, -16.2) -> (213.8, -14.2)
  line L2 (213.8, -14.2) -> (0.2, -14.2)
  line L3 (0.2, -14.2) -> (0.2, -16.2)
extrude "Front cover" add sketch "Front cover outline" along normal blind 97.6 separate body makes body 21 in component "02 Snap-on front cover - PRINT"
ref_plane "WorkPlane2" through (0, 0, 69.1) normal (0, 0, 1) x (1, 0, 0) in component "02 Snap-on front cover - PRINT"
sketch "Clearance over integral camera root outline" plane through (0, 0, 69.1) normal (0, 0, 1) x (1, 0, 0) in component "02 Snap-on front cover - PRINT"
  line L0 (85.6, -16.3) -> (128.4, -16.3)
  line L1 (128.4, -16.3) -> (128.4, -14.1)
  line L2 (128.4, -14.1) -> (85.6, -14.1)
  line L3 (85.6, -14.1) -> (85.6, -16.3)
extrude "Clearance over integral camera root" cut sketch "Clearance over integral camera root outline" along normal blind 3.4 bodies 21 in component "02 Snap-on front cover - PRINT"
ref_plane "WorkPlane3" through (0, 0, 112) normal (0, 0, 1) x (1, 0, 0) in component "02 Snap-on front cover - PRINT"
sketch "Front air slot 12 outline" plane through (0, 0, 112) normal (0, 0, 1) x (1, 0, 0) in component "02 Snap-on front cover - PRINT"
  line L0 (12, -16.3) -> (16, -16.3)
  line L1 (16, -16.3) -> (16, -14.1)
  line L2 (16, -14.1) -> (12, -14.1)
  line L3 (12, -14.1) -> (12, -16.3)
extrude "Front air slot 12" cut sketch "Front air slot 12 outline" along normal blind 40 bodies 21 in component "02 Snap-on front cover - PRINT"
ref_plane "WorkPlane4" through (0, 0, 112) normal (0, 0, 1) x (1, 0, 0) in component "02 Snap-on front cover - PRINT"
sketch "Front air slot 24 outline" plane through (0, 0, 112) normal (0, 0, 1) x (1, 0, 0) in component "02 Snap-on front cover - PRINT"
  line L0 (24, -16.3) -> (28, -16.3)
  line L1 (28, -16.3) -> (28, -14.1)
  line L2 (28, -14.1) -> (24, -14.1)
  line L3 (24, -14.1) -> (24, -16.3)
extrude "Front air slot 24" cut sketch "Front air slot 24 outline" along normal blind 40 bodies 21 in component "02 Snap-on front cover - PRINT"
ref_plane "WorkPlane5" through (0, 0, 112) normal (0, 0, 1) x (1, 0, 0) in component "02 Snap-on front cover - PRINT"
sketch "Front air slot 36 outline" plane through (0, 0, 112) normal (0, 0, 1) x (1, 0, 0) in component "02 Snap-on front cover - PRINT"
  line L0 (36, -16.3) -> (40, -16.3)
  line L1 (40, -16.3) -> (40, -14.1)
  line L2 (40, -14.1) -> (36, -14.1)
  line L3 (36, -14.1) -> (36, -16.3)
extrude "Front air slot 36" cut sketch "Front air slot 36 outline" along normal blind 40 bodies 21 in component "02 Snap-on front cover - PRINT"
ref_plane "WorkPlane6" through (0, 0, 112) normal (0, 0, 1) x (1, 0, 0) in component "02 Snap-on front cover - PRINT"
sketch "Front air slot 48 outline" plane through (0, 0, 112) normal (0, 0, 1) x (1, 0, 0) in component "02 Snap-on front cover - PRINT"
  line L0 (48, -16.3) -> (52, -16.3)
  line L1 (52, -16.3) -> (52, -14.1)
  line L2 (52, -14.1) -> (48, -14.1)
  line L3 (48, -14.1) -> (48, -16.3)
extrude "Front air slot 48" cut sketch "Front air slot 48 outline" along normal blind 40 bodies 21 in component "02 Snap-on front cover - PRINT"
ref_plane "WorkPlane7" through (0, 0, 112) normal (0, 0, 1) x (1, 0, 0) in component "02 Snap-on front cover - PRINT"
sketch "Front air slot 64 outline" plane through (0, 0, 112) normal (0, 0, 1) x (1, 0, 0) in component "02 Snap-on front cover - PRINT"
  line L0 (64, -16.3) -> (68, -16.3)
  line L1 (68, -16.3) -> (68, -14.1)
  line L2 (68, -14.1) -> (64, -14.1)
  line L3 (64, -14.1) -> (64, -16.3)
extrude "Front air slot 64" cut sketch "Front air slot 64 outline" along normal blind 40 bodies 21 in component "02 Snap-on front cover - PRINT"
ref_plane "WorkPlane8" through (0, 0, 112) normal (0, 0, 1) x (1, 0, 0) in component "02 Snap-on front cover - PRINT"
sketch "Front air slot 88 outline" plane through (0, 0, 112) normal (0, 0, 1) x (1, 0, 0) in component "02 Snap-on front cover - PRINT"
  line L0 (88, -16.3) -> (92, -16.3)
  line L1 (92, -16.3) -> (92, -14.1)
  line L2 (92, -14.1) -> (88, -14.1)
  line L3 (88, -14.1) -> (88, -16.3)
extrude "Front air slot 88" cut sketch "Front air slot 88 outline" along normal blind 40 bodies 21 in component "02 Snap-on front cover - PRINT"
ref_plane "WorkPlane9" through (0, 0, 112) normal (0, 0, 1) x (1, 0, 0) in component "02 Snap-on front cover - PRINT"
sketch "Front air slot 100 outline" plane through (0, 0, 112) normal (0, 0, 1) x (1, 0, 0) in component "02 Snap-on front cover - PRINT"
  line L0 (100, -16.3) -> (104, -16.3)
  line L1 (104, -16.3) -> (104, -14.1)
  line L2 (104, -14.1) -> (100, -14.1)
  line L3 (100, -14.1) -> (100, -16.3)
extrude "Front air slot 100" cut sketch "Front air slot 100 outline" along normal blind 40 bodies 21 in component "02 Snap-on front cover - PRINT"
ref_plane "WorkPlane10" through (0, 0, 112) normal (0, 0, 1) x (1, 0, 0) in component "02 Snap-on front cover - PRINT"
sketch "Front air slot 112 outline" plane through (0, 0, 112) normal (0, 0, 1) x (1, 0, 0) in component "02 Snap-on front cover - PRINT"
  line L0 (112, -16.3) -> (116, -16.3)
  line L1 (116, -16.3) -> (116, -14.1)
  line L2 (116, -14.1) -> (112, -14.1)
  line L3 (112, -14.1) -> (112, -16.3)
extrude "Front air slot 112" cut sketch "Front air slot 112 outline" along normal blind 40 bodies 21 in component "02 Snap-on front cover - PRINT"
ref_plane "WorkPlane11" through (0, 0, 112) normal (0, 0, 1) x (1, 0, 0) in component "02 Snap-on front cover - PRINT"
sketch "Front air slot 140 outline" plane through (0, 0, 112) normal (0, 0, 1) x (1, 0, 0) in component "02 Snap-on front cover - PRINT"
  line L0 (140, -16.3) -> (144, -16.3)
  line L1 (144, -16.3) -> (144, -14.1)
  line L2 (144, -14.1) -> (140, -14.1)
  line L3 (140, -14.1) -> (140, -16.3)
extrude "Front air slot 140" cut sketch "Front air slot 140 outline" along normal blind 40 bodies 21 in component "02 Snap-on front cover - PRINT"
ref_plane "WorkPlane12" through (0, 0, 112) normal (0, 0, 1) x (1, 0, 0) in component "02 Snap-on front cover - PRINT"
sketch "Front air slot 152 outline" plane through (0, 0, 112) normal (0, 0, 1) x (1, 0, 0) in component "02 Snap-on front cover - PRINT"
  line L0 (152, -16.3) -> (156, -16.3)
  line L1 (156, -16.3) -> (156, -14.1)
  line L2 (156, -14.1) -> (152, -14.1)
  line L3 (152, -14.1) -> (152, -16.3)
extrude "Front air slot 152" cut sketch "Front air slot 152 outline" along normal blind 40 bodies 21 in component "02 Snap-on front cover - PRINT"
ref_plane "WorkPlane13" through (0, 0, 112) normal (0, 0, 1) x (1, 0, 0) in component "02 Snap-on front cover - PRINT"
sketch "Front air slot 164 outline" plane through (0, 0, 112) normal (0, 0, 1) x (1, 0, 0) in component "02 Snap-on front cover - PRINT"
  line L0 (164, -16.3) -> (168, -16.3)
  line L1 (168, -16.3) -> (168, -14.1)
  line L2 (168, -14.1) -> (164, -14.1)
  line L3 (164, -14.1) -> (164, -16.3)
extrude "Front air slot 164" cut sketch "Front air slot 164 outline" along normal blind 40 bodies 21 in component "02 Snap-on front cover - PRINT"
ref_plane "WorkPlane14" through (0, 0, 112) normal (0, 0, 1) x (1, 0, 0) in component "02 Snap-on front cover - PRINT"
sketch "Front air slot 176 outline" plane through (0, 0, 112) normal (0, 0, 1) x (1, 0, 0) in component "02 Snap-on front cover - PRINT"
  line L0 (176, -16.3) -> (180, -16.3)
  line L1 (180, -16.3) -> (180, -14.1)
  line L2 (180, -14.1) -> (176, -14.1)
  line L3 (176, -14.1) -> (176, -16.3)
extrude "Front air slot 176" cut sketch "Front air slot 176 outline" along normal blind 40 bodies 21 in component "02 Snap-on front cover - PRINT"
ref_plane "WorkPlane15" through (0, 0, 112) normal (0, 0, 1) x (1, 0, 0) in component "02 Snap-on front cover - PRINT"
sketch "Front air slot 188 outline" plane through (0, 0, 112) normal (0, 0, 1) x (1, 0, 0) in component "02 Snap-on front cover - PRINT"
  line L0 (188, -16.3) -> (192, -16.3)
  line L1 (192, -16.3) -> (192, -14.1)
  line L2 (192, -14.1) -> (188, -14.1)
  line L3 (188, -14.1) -> (188, -16.3)
extrude "Front air slot 188" cut sketch "Front air slot 188 outline" along normal blind 40 bodies 21 in component "02 Snap-on front cover - PRINT"
ref_plane "WorkPlane16" through (0, 0, 71.75) normal (0, 0, 1) x (1, 0, 0) in component "02 Snap-on front cover - PRINT"
sketch "Bottom locating tab 15 outline" plane through (0, 0, 71.75) normal (0, 0, 1) x (1, 0, 0) in component "02 Snap-on front cover - PRINT"
  line L0 (15, -14.2) -> (35, -14.2)
  line L1 (35, -14.2) -> (35, -10.8)
  line L2 (35, -10.8) -> (15, -10.8)
  line L3 (15, -10.8) -> (15, -14.2)
extrude "Bottom locating tab 15" add sketch "Bottom locating tab 15 outline" along normal blind 1.2 bodies 21 in component "02 Snap-on front cover - PRINT"
ref_plane "WorkPlane17" through (0, 0, 163) normal (0, 0, 1) x (1, 0, 0) in component "02 Snap-on front cover - PRINT"
sketch "Top locating tab 15 outline" plane through (0, 0, 163) normal (0, 0, 1) x (1, 0, 0) in component "02 Snap-on front cover - PRINT"
  line L0 (15, -14.2) -> (35, -14.2)
  line L1 (35, -14.2) -> (35, -10.8)
  line L2 (35, -10.8) -> (15, -10.8)
  line L3 (15, -10.8) -> (15, -14.2)
extrude "Top locating tab 15" add sketch "Top locating tab 15 outline" along normal blind 1.25 bodies 21 in component "02 Snap-on front cover - PRINT"
ref_plane "WorkPlane18" through (0, 0, 71.75) normal (0, 0, 1) x (1, 0, 0) in component "02 Snap-on front cover - PRINT"
sketch "Bottom locating tab 180 outline" plane through (0, 0, 71.75) normal (0, 0, 1) x (1, 0, 0) in component "02 Snap-on front cover - PRINT"
  line L0 (180, -14.2) -> (200, -14.2)
  line L1 (200, -14.2) -> (200, -10.8)
  line L2 (200, -10.8) -> (180, -10.8)
  line L3 (180, -10.8) -> (180, -14.2)
extrude "Bottom locating tab 180" add sketch "Bottom locating tab 180 outline" along normal blind 1.2 bodies 21 in component "02 Snap-on front cover - PRINT"
ref_plane "WorkPlane19" through (0, 0, 163) normal (0, 0, 1) x (1, 0, 0) in component "02 Snap-on front cover - PRINT"
sketch "Top locating tab 180 outline" plane through (0, 0, 163) normal (0, 0, 1) x (1, 0, 0) in component "02 Snap-on front cover - PRINT"
  line L0 (180, -14.2) -> (200, -14.2)
  line L1 (200, -14.2) -> (200, -10.8)
  line L2 (200, -10.8) -> (180, -10.8)
  line L3 (180, -10.8) -> (180, -14.2)
extrude "Top locating tab 180" add sketch "Top locating tab 180 outline" along normal blind 1.25 bodies 21 in component "02 Snap-on front cover - PRINT"
ref_plane "WorkPlane20" through (52.5, 0, 0) normal (1, 0, 0) x (0, 1, 0) in component "02 Snap-on front cover - PRINT"
sketch "Bottom cover snap 55 outline" plane through (52.5, 0, 0) normal (1, 0, 0) x (0, 0, -1) in component "02 Snap-on front cover - PRINT"
  line L0 (-71.75, -14.2) -> (-72.95, -14.2)
  line L1 (-72.95, -14.2) -> (-72.95, -1.8)
  line L2 (-72.95, -1.8) -> (-71.75, -1.8)
  line L3 (-71.75, -1.8) -> (-70.8, -3.2)
  line L4 (-70.8, -3.2) -> (-70.8, -4)
  line L5 (-70.8, -4) -> (-71.75, -4)
  line L6 (-71.75, -4) -> (-71.75, -14.2)
extrude "Bottom cover snap 55" add sketch "Bottom cover snap 55 outline" along normal blind 5 bodies 21 in component "02 Snap-on front cover - PRINT"
ref_plane "WorkPlane21" through (52.5, 0, 0) normal (1, 0, 0) x (0, 1, 0) in component "02 Snap-on front cover - PRINT"